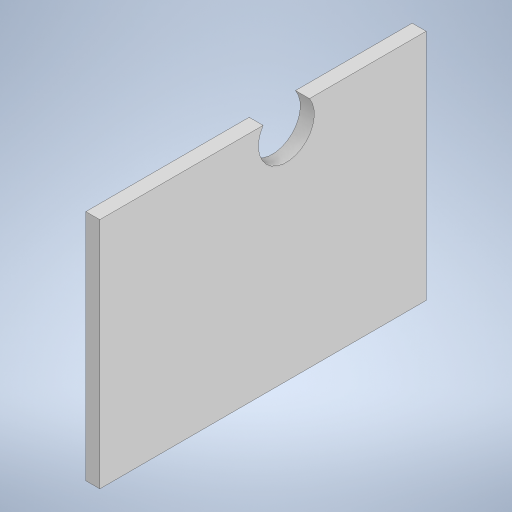
# Autodesk Inventor part: support_capteur
Saved by Autodesk Inventor 2024.3 (Build 283343000, 343)
## iProperties
Created: 2025-05-13
Part Number: support_capteur
Material: Générique
Document SubType Name: Modeling
Designer: abouabdellah
Density: 1 g/cm^3
Appearance: Par défaut
Author: abouabdellah
Autodesk Inventor part; units mm, degrees
ref_plane "YZ Plane" through (0, 0, 0) normal (1, 0, 0) x (0, 1, 0)
ref_plane "XZ Plane" through (0, 0, 0) normal (0, 1, 0) x (-1, 0, 0)
ref_plane "XY Plane" through (0, 0, 0) normal (0, 0, 1) x (1, 0, 0)
sketch "Esquisse1" plane through (0, 0, 0) normal (1, 0, 0) x (0, 1, 0)
  line L0 (22.3651, 27.3755) -> (-27.6349, 27.3755)
  line L1 (-27.6349, 27.3755) -> (-27.6349, -42.6245)
  line L2 (-27.6349, -42.6245) -> (22.3651, -42.6245)
  line L3 (22.3651, -42.6245) -> (22.3651, 27.3755)
  point P0 (0, 0)
  dimension "d0" = 70
  dimension "d1" = 50
  constraints: 8 end point, 2 parallel, 1 horizontal, 1 perpendicular
  measures "d0" distance of L2.end L0.start
  measures "d1" distance of L0.start L0.end
extrude "Extrusion1" add sketch "Esquisse1" along normal blind 3
sketch "Esquisse2" plane through (3, 0, 0) normal (1, 0, 0) x (0, 0, -1)
  line L0 (42.6245, 22.3651) -> (-27.3755, 22.3651) projected
  circle A0 centre (12.6245, 19) radius 6
  point P0 (0, 0)
  point P1 (7.657, 22.3651)
  point P2 (17.592, 22.3651)
  dimension "d7" = 12
  dimension "d8" = 19
  constraints: 1 centre point
  measures "d7" diameter of A0
  measures "d8" vertical distance of point (0, 0) A0.centre
extrude "Extrusion2" cut sketch "Esquisse2" against normal blind 3 contours A0 L0 picked at (14.4167, 19.4741)
